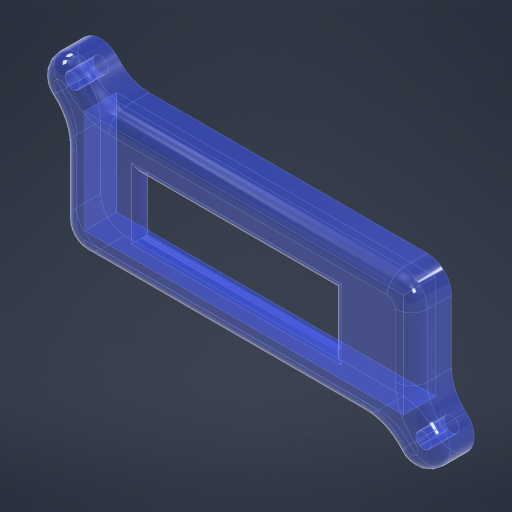
# Autodesk Inventor part: Frame_LCD
Saved by Autodesk Inventor 2024.3 (Build 283343000, 343)
## iProperties
Created: 2026-07-02
Part Number: Frame_LCD
Material: Generic
Document SubType Name: Modeling
Designer: REMOTE
Density: 1 g/cm^3
Appearance: Clear - Blue
Author: REMOTE
Autodesk Inventor part; units mm, degrees
ref_plane "YZ Plane" through (0, 0, 0) normal (1, 0, 0) x (0, 1, 0)
ref_plane "XZ Plane" through (0, 0, 0) normal (0, 1, 0) x (-1, 0, 0)
ref_plane "XY Plane" through (0, 0, 0) normal (0, 0, 1) x (1, 0, 0)
sketch "Sketch1" plane through (0, 0, 0) normal (0, 0, 1) x (1, 0, 0)
  line L0 (11.8859, -2.3495) -> (11.8859, 3.1877) projected
  line L1 (11.8859, 3.1877) -> (-10.9728, 3.1877) projected
  line L2 (-10.9728, 3.1877) -> (-10.9728, -2.3495) projected
  line L3 (-10.9728, -2.3495) -> (11.8859, -2.3495) projected
  line L4 (12.4859, -2.9495) -> (12.4859, 3.7877)
  line L5 (12.4859, 3.7877) -> (-11.5728, 3.7877)
  line L6 (-11.5728, 3.7877) -> (-11.5728, -2.9495)
  line L7 (-11.5728, -2.9495) -> (12.4859, -2.9495)
  line L8 (-19.0246, -6.0452) -> (19.812, -6.0452)
  line L9 (19.812, -6.0452) -> (19.812, 6.0452)
  line L10 (19.812, 6.0452) -> (-19.0246, 6.0452)
  line L11 (-19.0246, 6.0452) -> (-19.0246, -6.0452)
  line L12 (-19.4246, 6.4452) -> (20.212, 6.4452)
  line L13 (20.212, 6.4452) -> (20.212, -6.4452)
  line L14 (20.212, -6.4452) -> (-19.4246, -6.4452)
  line L15 (-19.4246, -6.4452) -> (-19.4246, 6.4452)
  point P0 (0, 0)
  dimension "d0" = 0.6
  dimension "d1" = 0.4
  constraints: 24 end point, 4 parallel, 2 perpendicular, 1 horizontal, 7 other
  measures "d0" distance between parallel lines of L3 L7
  measures "d1" distance between parallel lines of L10 L12
extrude "Extrusion1" add sketch "Sketch1" along normal blind 1 contours L11 L10 L9 L8 | L12 L13 L14 L15
sketch "Sketch2" plane through (0, 0, 0) normal (0, 0, -1) x (-1, 0, 0)
  line L0 (19.4246, -6.4452) -> (-20.212, -6.4452) projected
  line L1 (19.4246, 6.4452) -> (19.4246, -6.4452) projected
  line L2 (-20.212, 6.4452) -> (19.4246, 6.4452) projected
  line L3 (-20.212, -6.4452) -> (-20.212, 6.4452) projected
  line L4 (-12.4859, -2.9495) -> (11.5728, -2.9495) projected
  line L5 (-12.4859, 3.7877) -> (-12.4859, -2.9495) projected
  line L6 (11.5728, 3.7877) -> (-12.4859, 3.7877) projected
  line L7 (11.5728, -2.9495) -> (11.5728, 3.7877) projected
  line L8 (21.4246, 8.4452) -> (21.4246, -8.4452)
  line L9 (21.4246, -8.4452) -> (-22.212, -8.4452)
  line L10 (-22.212, -8.4452) -> (-22.212, 8.4452)
  line L11 (-22.212, 8.4452) -> (21.4246, 8.4452)
  point P0 (0, 0)
  dimension "d4" = 2
  constraints: 8 end point, 3 other
  measures "d4" distance between parallel lines of L2 L11
extrude "Extrusion2" add sketch "Sketch2" along normal blind 4 and the other way blind 1 contours L8 L9 L10 L11
sketch "Sketch3" plane through (0, 0, 1) normal (0, 0, 1) x (1, 0, 0)
  line L0 (22.212, 8.4452) -> (-21.4246, 8.4452) projected
  circle A0 centre (-21.4246, 8.4452) radius 0.95
  line L1 (20.212, 6.4452) -> (-19.4246, 6.4452) projected
  circle A1 centre (-21.4246, 8.4452) radius 2.8284
  circle A2 centre (22.212, -8.4452) radius 0.95
  circle A3 centre (22.212, -8.4452) radius 2.8284
  point P0 (0, 0)
  point P1 (20.212, -6.4452)
  dimension "d9" = 1.9
  dimension "d10" = 1.9
  constraints: 3 coincident, 2 centre point, 6 other
  measures "d9" diameter of A0
  measures "d10" diameter of A2
extrude "Extrusion3" add sketch "Sketch3" against normal up to surface (5 mm away)
sketch "Sketch4" plane through (0, 0, 1) normal (0, 0, 1) x (1, 0, 0)
  line L0 (-21.4246, 8.4452) -> (-21.4246, 7.4952) projected
  circle A0 centre (-21.4246, 8.4452) radius 0.95
  circle A1 centre (22.212, -8.4452) radius 0.95
  point P0 (0, 0)
  dimension "d13" = 1.9
  dimension "d14" = 1.9
  constraints: 2 centre point
  measures "d13" diameter of A0
  measures "d14" diameter of A1
extrude "Extrusion4" cut sketch "Sketch4" against normal up to surface (5 mm away)
fillet "Fillet1" radius 5 4 edges at (-21.4246, 5.6168, -1.5) (-18.5962, 8.4452, -1.5) (19.3836, -8.4452, -1.5) (22.212, -5.6168, -1.5)
sketch "Sketch5" plane through (0, 0, 1) normal (0, 0, 1) x (1, 0, 0)
  circle A0 centre (-21.4246, 8.4452) radius 0.95 projected
  circle A1 centre (22.212, -8.4452) radius 0.95 projected
  point P0 (0, 0)
extrude "Extrusion5" add sketch "Sketch5" against normal blind 1.5
fillet "Fillet2" radius 2 10 edges at (-21.8987, 4.5467, 1) (-21.4246, -3.0118, 1) (-17.5261, 8.9193, 1) (3.4055, 8.4452, 1) (-23.4246, 10.4452, 1) (18.3135, -8.9193, 1) (24.212, -10.4452, 1) (22.6861, -4.5467, 1) (22.212, 3.0118, 1) (-2.6181, -8.4452, 1)
fillet "Fillet3" radius 1 4 edges at (0.4566, 3.7877, 1) (-11.5728, 0.4191, 1) (0.4566, -2.9495, 1) (12.4859, 0.4191, 1)
fillet "Fillet4" radius 3 4 edges at (22.212, 8.4452, -2.5) (21.6262, 7.8594, 0.4142) (-20.8388, -7.8594, 0.4142) (-21.4246, -8.4452, -2.5)
body "Solid1"
